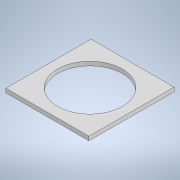
# Autodesk Inventor part: Suport_felinar_general_varianta_corecta_205_210_gaura_160
Saved by Autodesk Inventor 2022.6 (Build 266554000, 554)
## iProperties
Created: 2025-06-12
Part Number: Suport_felinar_general_varianta_corecta_205_210_gaura_160
Material: Generic
Document SubType Name: Modeling
Designer: Dragos Macovei
Density: 1 g/cm^3
Appearance: Default
Author: Dragos Macovei
Autodesk Inventor part; units mm, degrees
ref_plane "YZ Plane" through (0, 0, 0) normal (1, 0, 0) x (0, 1, 0)
ref_plane "XZ Plane" through (0, 0, 0) normal (0, 1, 0) x (-1, 0, 0)
ref_plane "XY Plane" through (0, 0, 0) normal (0, 0, 1) x (1, 0, 0)
sketch "Sketch1" plane through (0, 0, 0) normal (0, 1, 0) x (-1, 0, 0)
  circle A0 centre (0, 0) radius 80
  line L0 (102.5, 105) -> (-102.5, 105)
  line L1 (-102.5, 105) -> (-102.5, -105)
  line L2 (-102.5, -105) -> (102.5, -105)
  line L3 (102.5, -105) -> (102.5, 105)
  dimension "d0" = 160
  dimension "d2" = 205
  dimension "d3" = 210
  dimension "d4" = 105
  dimension "d7" = 102.5
  constraints: 8 end point, 2 parallel, 1 centre point, 1 coincident, 1 horizontal, 1 perpendicular
  measures "d0" diameter of A0
  measures "d2" distance of L2.end L1.end
  measures "d3" distance of L1.end L0.end
  measures "d4" distance from line of point (0, 0) L0
  measures "d7" distance from line of point (0, 0) L3
extrude "Extrusion1" add sketch "Sketch1" along normal blind 10
body "Solid1"
